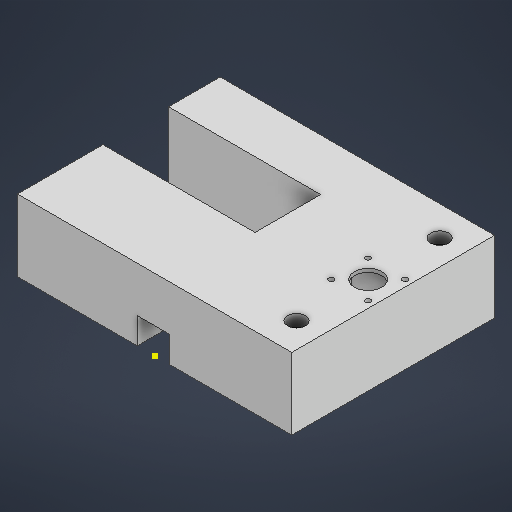
# Autodesk Inventor part: Base
Saved by Autodesk Inventor 2027.1 (Build 311270010, 270A)
## iProperties
Created: 2026-10-09
Part Number: Base
Material: Generic
Document SubType Name: Modeling
Designer: khaar
Density: 1 g/cm^3
Appearance: Default
Author: khaar
Autodesk Inventor part; units mm, degrees
ref_plane "YZ Plane" through (0, 0, 0) normal (1, 0, 0) x (0, 1, 0)
ref_plane "XZ Plane" through (0, 0, 0) normal (0, 1, 0) x (-1, 0, 0)
ref_plane "XY Plane" through (0, 0, 0) normal (0, 0, 1) x (1, 0, 0)
sketch "Sketch1" plane through (0, 0, 0) normal (0, 1, 0) x (-1, 0, 0)
  line L0 (115, 85) -> (-115, 85)
  line L1 (-115, 85) -> (-115, -85)
  line L2 (-115, -85) -> (115, -85)
  line L3 (115, -85) -> (115, 85)
  line L4 (115, 85) -> (-115, -85) construction
  line L5 (-115, 85) -> (115, -85) construction
  point P0 (0, 0)
  dimension "d0" = 170
  dimension "d1" = 230
  constraints: 12 end point, 2 midpoint, 2 parallel, 1 horizontal, 1 perpendicular
  measures "d0" distance of L2.end L0.start
  measures "d1" distance of L0.start L0.end
extrude "Extrusion1" add sketch "Sketch1" along normal blind 60
sketch "Sketch6" plane through (0, 60, 0) normal (0, 1, 0) x (1, 0, 0)
  line L0 (-115, -85) -> (115, -85) projected
  line L1 (94, -85) -> (94, 82.2034) construction
  line L2 (115, -85) -> (115, 85) projected
  circle A0 centre (94, 60) radius 7.5
  circle A1 centre (94, 0) radius 11.5
  circle A2 centre (94, -60) radius 7.5
  line L3 (115, 85) -> (-115, 85) projected
  circle A3 centre (94, 0) radius 21.9 construction
  line L4 (94, -21.9) -> (94, 0) construction
  line L5 (94, 0) -> (78.5144, -15.4856) construction
  circle A4 centre (78.5144, -15.4856) radius 2.25
  line L6 (94, 0) -> (109.4856, -15.4856) construction
  circle A5 centre (109.4856, -15.4856) radius 2.25
  line L7 (94, 0) -> (109.4856, 15.4856) construction
  circle A6 centre (109.4856, 15.4856) radius 2.25
  line L8 (94, 0) -> (78.5144, 15.4856) construction
  circle A7 centre (78.5144, 15.4856) radius 2.25
  point P0 (0, 0)
  dimension "d36" = 21
  dimension "d37" = 15
  dimension "d38" = 15
  dimension "d39" = 25
  dimension "d40" = 25
  dimension "d41" = 23
  dimension "d42" = 43.8
  dimension "d43" = 45
  dimension "d44" = 4.5
  dimension "d47" = 360
  constraints: 12 end point, 8 centre point, 7 coincident, 5 point on line, 2 point on circle, 1 collinear, 1 vertical, 19 other
  measures "d36" distance between parallel lines of L1 L2
  measures "d37" diameter of A2
  measures "d38" diameter of A0
  measures "d39" distance from line of L0 A2.centre
  measures "d40" distance from line of L3 A0.centre
  measures "d41" diameter of A1
  measures "d42" diameter of A3
  measures "d43" angle of L5 L1
  measures "d44" diameter of A4
extrude "Extrusion6" cut sketch "Sketch6" against normal blind 10
sketch "Sketch7" plane through (0, 0, 0) normal (0, -1, 0) x (1, 0, 0)
  line L0 (50, -30) -> (114.136, -30)
  line L1 (114.136, -30) -> (114.136, 30)
  line L2 (114.136, 30) -> (50, 30)
  line L3 (50, 30) -> (50, -30)
  line L4 (50, -30) -> (114.136, 30) construction
  line L5 (114.136, -30) -> (50, 30) construction
  line L6 (115, 85) -> (115, -85) projected
  line L7 (115, -85) -> (-115, -85) projected
  point P0 (0, 0)
  point P1 (82.068, 0)
  dimension "d51" = 60
  dimension "d52" = 64.136
  dimension "d53" = 0.864
  dimension "d91" = 55
  constraints: 12 end point, 2 midpoint, 2 parallel, 1 horizontal, 1 perpendicular
  measures "d51" distance of L2.end L0.start
  measures "d52" distance of L1.end L2.end
  measures "d53" distance between parallel lines of L6 L1
  measures "d91" distance between parallel lines of L7 L0
extrude "Extrusion7" cut sketch "Sketch7" against normal blind 57
sketch "Sketch9" plane through (-115, 0, 85) normal (0, 0, 1) x (1, 0, 0)
  point P0 (115, 0)
sketch "Sketch10" plane through (-115, 0, 85) normal (0, 0, 1) x (1, 0, 0)
  line L0 (0, 0) -> (230, 0) projected
  line L1 (73.9351, 0) -> (127.5, 0)
  line L2 (127.5, 0) -> (127.5, 21.9457)
  line L3 (127.5, 21.9457) -> (100.5, 21.9457)
  line L4 (100.5, 21.9457) -> (100.5, 0)
  line L5 (100.5, 0) -> (47.9351, 0)
  line L6 (230, 0) -> (230, 60) projected
  point P0 (115, 0)
  dimension "d59" = 27
  dimension "d60" = 102.5
  constraints: 10 end point, 4 point on line, 1 collinear, 1 horizontal, 1 perpendicular, 1 vertical
  measures "d59" distance of L2.end L3.end
  measures "d60" distance between parallel lines of L6 L2
extrude "Extrusion8" cut sketch "Sketch10" against normal blind 170
sketch "Sketch12" plane through (-115, 0, -85) normal (-1, 0, 0) x (0, 0, 1)
  point P0 (85, 0)
sketch "Sketch15" plane through (115, 60, -85) normal (0, 0, -1) x (-1, 0, 0)
  line L0 (170, -54) -> (103.5, -54) projected
  line L1 (230, -60) -> (230, 0) projected
  line L2 (185, -42) -> (205, -42)
  line L3 (205, -42) -> (205, -52)
  line L4 (205, -52) -> (185, -52)
  line L5 (185, -52) -> (185, -42)
  point P0 (115, -60)
  point P1 (149.055, -54)
  dimension "d85" = 20
  dimension "d86" = 10
  dimension "d87" = 2
  dimension "d88" = 25
  constraints: 8 end point, 2 parallel, 1 horizontal, 1 perpendicular, 1 point on line, 1 other
  measures "d85" distance of L2.start L2.end
  measures "d86" distance of L2.end L3.end
  measures "d87" distance between parallel lines of L0 L4
extrude "Extrusion13" cut sketch "Sketch15" against normal blind 10
sketch "Sketch16" plane through (-115, 0, -85) normal (-1, 0, 0) x (0, 0, 1)
  line L0 (0, 0) -> (170, 0) projected
  line L1 (43.3, 60) -> (98.3, 60)
  line L2 (98.3, 60) -> (98.3, 0)
  line L3 (98.3, 0) -> (43.3, 0)
  line L4 (43.3, 0) -> (43.3, 60)
  line L5 (170, 0) -> (170, 60) projected
  point P0 (85, 0)
  dimension "d95" = 55
  dimension "d96" = 71.7
  constraints: 8 end point, 2 parallel, 1 horizontal, 1 perpendicular, 1 point on line
  measures "d95" distance of L1.start L1.end
  measures "d96" distance between parallel lines of L5 L2
extrude "Extrusion14" cut sketch "Sketch16" against normal blind 127.5
body "Solid1"
